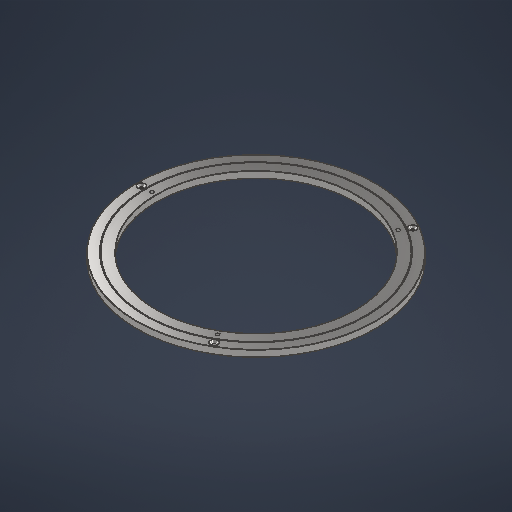
# Autodesk Inventor part: 300PI Turntable
Saved by Autodesk Inventor 2026.2 (Build 302298010, 298A)
## iProperties
Created: 2026-05-07
Part Number: 300PI Turntable
Material: 스테인리스스틸
Document SubType Name: Modeling
Designer: work
Density: 8 g/cm^3
Appearance: 반연마
Author: work
Autodesk Inventor part; units mm, degrees
ref_plane "YZ Plane" through (0, 0, 0) normal (1, 0, 0) x (0, 1, 0)
ref_plane "XZ Plane" through (0, 0, 0) normal (0, 1, 0) x (-1, 0, 0)
sketch "스케치1" plane through (0, 0, 0) normal (0, 1, 0) x (-1, 0, 0)
  circle A0 centre (0, 0) radius 150
  circle A1 centre (0, 0) radius 125
  dimension "d0" = 300
  dimension "d1" = 250
  constraints: 2 centre point, 2 coincident
  measures "d0" diameter of A0
  measures "d1" diameter of A1
extrude "돌출1" add sketch "스케치1" along normal blind 8.35
sketch "스케치2" plane through (0, 8.35, 0) normal (0, 1, 0) x (1, 0, 0)
  circle A0 centre (0, 0) radius 130.75 construction
  line L0 (0, 0) -> (-130.75, 0) construction
  circle A1 centre (0, 0) radius 125 projected
  circle A2 centre (-130.75, 0) radius 2.25
  line L1 (-130.75, 0) -> (-150, 0) construction
  circle A3 centre (0, 0) radius 150 projected
  circle A4 centre (-143.75, 0) radius 2.25
  circle A5 centre (0, 0) radius 138
  circle A6 centre (0, 0) radius 138.5
  point P0 (-125, 0)
  dimension "d4" = 4.5
  dimension "d5" = 5.75
  dimension "d6" = 4.5
  dimension "d7" = 6.25
  dimension "d8" = 12
  dimension "d9" = 0.5
  constraints: 5 coincident, 4 centre point, 4 end point, 3 horizontal alignment, 2 horizontal, 2 point on line, 4 other
  measures "d4" diameter of A2
  measures "d5" distance of point (-125, 0) L0.end
  measures "d6" diameter of A4
  measures "d7" distance of L1.end A4.centre
  measures "d9" radial gap between concentric circles of A6 A5
extrude "돌출2" cut sketch "스케치2" against normal through all contours A2 | A4
extrude "돌출3" cut sketch "스케치2" against normal blind 2 contours A6
ref_plane "작업 평면1" through (0, 4.175, 0) normal (0, 1, 0) x (1, 0, 0)
mirror "미러1" about plane through (0, 4.175, 0) normal (0, 1, 0) of "돌출3"
pattern_circular "원형 패턴1" count 3 over 360 about axis through (0, -10, 0) along (0, 1, 0) of "돌출2"
chamfer "모따기1" distance 0.25 angle 45 8 edges at (150, 8.35, 0) (-138.5, 8.35, 0) (150, 0, 0) (-138.5, 0, 0) (-138, 0, 0) (125, 0, 0) (-138, 8.35, 0) (125, 8.35, 0)
chamfer "모따기2" distance 2.5 angle 45 3 edges at (-146, 8.35, 0) (73, 8.35, 126.4397) (73, 8.35, -126.4397)
chamfer "모따기3" distance 2.5 angle 45 3 edges at (66.5, 0, 115.1814) (66.5, 0, -115.1814) (-133, 0, 0)
ref_plane "작업 평면2" through (0, 4.175, 0) normal (0, 1, 0) x (1, 0, 0)
